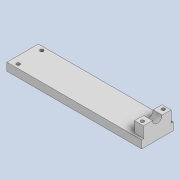
# Autodesk Inventor part: крепление 1
Saved by Autodesk Inventor 2021.2 (Build 252289000, 289)
## iProperties
Created: 2026-11-16
Part Number: крепление 1
Material: Типовые
Document SubType Name: Modeling
Designer: ritar
Density: 1 g/cm^3
Appearance: По умолчанию
Author: ritar
Autodesk Inventor part; units mm, degrees
ref_plane "YZ Plane" through (0, 0, 0) normal (1, 0, 0) x (0, 1, 0)
ref_plane "XZ Plane" through (0, 0, 0) normal (0, 1, 0) x (-1, 0, 0)
ref_plane "XY Plane" through (0, 0, 0) normal (0, 0, 1) x (1, 0, 0)
sketch "Эскиз1" plane through (0, 0, 0) normal (0, 1, 0) x (-1, 0, 0)
  line L0 (0, 14) -> (10, 14)
  line L1 (10, 14) -> (10, -14)
  line L2 (10, -14) -> (0, -14)
  line L3 (0, -14) -> (0, 14)
  line L4 (0, 0) -> (5, 0) construction
  circle A0 centre (3.5, -10.5) radius 1.5
  circle A1 centre (3.5, 10.5) radius 1.5
  line L5 (0, 14) -> (-110, 14)
  line L6 (-110, 14) -> (-110, -14)
  line L7 (-110, -14) -> (0, -14)
  line L8 (0, -14) -> (0, 14)
  dimension "d0" = 10
  dimension "d1" = 28
  dimension "d2" = 14
  dimension "d3" = 3
  dimension "d4" = 3.5
  dimension "d5" = 3.5
  dimension "d6" = 110
  dimension "d7" = 28
  constraints: 18 end point, 4 parallel, 3 horizontal, 2 centre point, 2 perpendicular, 1 midpoint, 1 symmetric about line, 1 other
  measures "d0" distance of L1.end L2.end
  measures "d1" distance of L2.end L0.start
  measures "d2" distance between parallel lines of L4 L2
  measures "d3" diameter of A0
  measures "d4" distance from line of L3 A0.centre
  measures "d5" distance from line of L2 A0.centre
  measures "d6" distance of L6.end L7.end
  measures "d7" distance between parallel lines of L5 L7
extrude "Выдавливание1" add sketch "Эскиз1" along normal blind 7
sketch "Эскиз2" plane through (110, 0, 14) normal (1, 0, 0) x (0, 0, -1)
  circle A0 centre (14, 17) radius 4.25
  line L0 (0, 0) -> (28, 0) projected
  line L1 (0, 7) -> (28, 7) projected
  line L2 (9.75, 17) -> (1.75, 17)
  line L3 (1.75, 17) -> (1.75, 7)
  line L4 (28, 7) -> (0, 7) projected
  line L5 (18.25, 17) -> (26.25, 17)
  line L6 (26.25, 17) -> (26.25, 7)
  point P0 (14, 0)
  point P1 (14, 0)
  point P2 (1.75, 7)
  point P3 (26.25, 7)
  dimension "d10" = 8.5
  dimension "d11" = 10
  dimension "d12" = 8
  dimension "d13" = 8
  dimension "d14" = 10
  constraints: 8 end point, 4 point on line, 2 perpendicular, 2 point on circle, 1 centre point, 1 horizontal, 1 midpoint, 1 vertical alignment
  measures "d10" diameter of A0
  measures "d11" distance from line of L1 A0.centre
  measures "d12" distance of L5.start L5.end
  measures "d13" distance of L2.start L2.end
  measures "d14" distance of L5.end L6.end
extrude "Выдавливание2" add sketch "Эскиз2" against normal blind 8 contours L5 L6 L1 L3 L2 A0
sketch "Эскиз3" plane through (110, 17, -4.25) normal (0, 1, 0) x (1, 0, 0)
  circle A0 centre (-4, -13.5) radius 1.5
  circle A1 centre (-4, 5) radius 1.5
  line L0 (0, -16.5) -> (-8, -16.5) projected
  line L1 (0, -8.5) -> (0, -16.5) projected
  line L2 (0, 8) -> (-8, 8) projected
  line L3 (0, 8) -> (0, 0) projected
  point P0 (-110, -4.25)
  dimension "d17" = 3
  dimension "d18" = 3
  dimension "d19" = 3
  dimension "d20" = 4
  dimension "d21" = 3
  dimension "d22" = 4
  constraints: 2 centre point
  measures "d17" diameter of A0
  measures "d18" diameter of A1
  measures "d19" distance from line of L0 A0.centre
  measures "d20" distance from line of L1 A0.centre
  measures "d21" distance from line of L2 A1.centre
  measures "d22" distance from line of L3 A1.centre
extrude "Выдавливание3" cut sketch "Эскиз3" against normal blind 8
